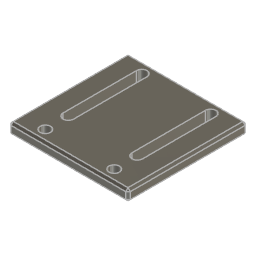
Spacer-Rear-Wedge_26x26mm_M2.5 (Autodesk Fusion 360 design; units mm, degrees)
part number: 2026-04-12-13-15-03-912
Autodesk Fusion 360 part; units mm, degrees
sketch "Sketch1" plane through (0, 0, 0) normal (0, 0, 1) x (1, 0, 0)
  line L0 (13, 11) -> (-13, 11)
  line L1 (-13, 11) -> (-13, -15)
  line L2 (-13, -15) -> (13, -15)
  line L3 (13, -15) -> (13, 11)
  circle A0 centre (-7.5, -12.5) radius 1.15
  circle A1 centre (7.5, -12.5) radius 1.15
  line L4 (-8.65, -7.5) -> (-8.65, 8.5)
  line L5 (-6.35, -7.5) -> (-6.35, 8.5)
  line L6 (6.35, -7.5) -> (6.35, 8.5)
  line L7 (8.65, -7.5) -> (8.65, 8.5)
  arc A2 (6.35, -7.5) -> (8.65, -7.5) centre (7.5, -7.5) ccw
  arc A3 (-8.65, -7.5) -> (-6.35, -7.5) centre (-7.5, -7.5) ccw
  arc A4 (-6.35, 8.5) -> (-8.65, 8.5) centre (-7.5, 8.5) ccw
  arc A5 (8.65, 8.5) -> (6.35, 8.5) centre (7.5, 8.5) ccw
  line L8 (-8.65, -7.5) -> (-8.65, 8.5)
  dimension "d8" = 2.3
  constraint horizontal L0
  constraint perpendicular L0 L1
  constraint parallel L0 L2
  constraint parallel L1 L3
  constraint tangent L4 A4
  constraint parallel L3 L4
  constraint tangent L5 A4
  constraint parallel L5 L8
  constraint tangent L6 A5
  constraint parallel L5 L6
  constraint tangent L7 A5
  constraint parallel L6 L7
  measures "d8" diameter of A0
extrude "Extrude1" add sketch "Sketch1" along normal blind 2.5
chamfer "Chamfer1" distance 0.5 angle 45 12 edges at (-13, -2, 2.5) (-13, -2, 0) (0, 11, 2.5) (0, 11, 0) (13, -2, 2.5) (13, -2, 0) (0, -15, 2.5) (0, -15, 0) (-13, -15, 1.25) (-13, 11, 1.25) (13, 11, 1.25) (13, -15, 1.25)
